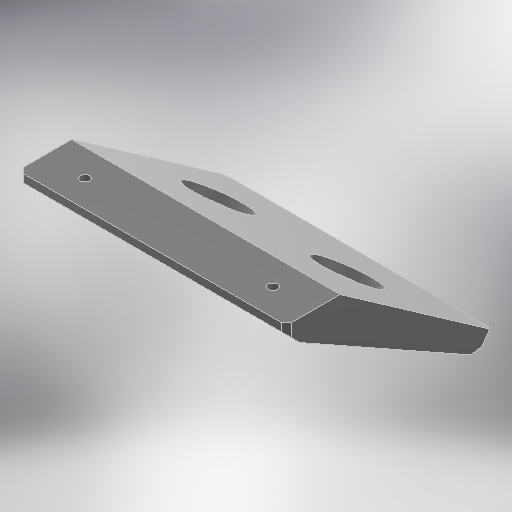
# Autodesk Inventor part: 3D_Estop-mount
Saved by Autodesk Inventor 2025.3 (Build 293356030, 356C)
## iProperties
Created: 2026-09-02
Part Number: 3D_Estop-mount
Material: 一般
Document SubType Name: Modeling
Designer: ibuki_ono
Density: 1 g/cm^3
Appearance: 滑らか - 黒
Author: ibuki_ono
## iProperties of the stored document 3D_Estop-mount_3D プリント.ipt
Created: 2026-09-04
Part Number: 3D_Estop-mount_3D プリント
Material: 一般
Document SubType Name: Modeling
Designer: ibuki_ono
Density: 1 g/cm^3
Appearance: 既定
Author: ibuki_ono
Autodesk Inventor part; units mm, degrees
ref_plane "YZ Plane" through (0, 0, 0) normal (1, 0, 0) x (0, 1, 0)
ref_plane "XZ Plane" through (0, 0, 0) normal (0, 1, 0) x (-1, 0, 0)
ref_plane "XY Plane" through (0, 0, 0) normal (0, 0, 1) x (1, 0, 0)
sketch "スケッチ1" plane through (0, 0, 0) normal (1, 0, 0) x (0, 1, 0)
  line L0 (0, 0) -> (-3, 0)
  line L1 (-3, 0) -> (-3, 20)
  line L2 (-3, 20) -> (0, 20)
  line L3 (0, 20) -> (0, 0)
  line L4 (0, 0) -> (-2.4575, 1.7207)
  line L5 (-2.4575, 1.7207) -> (-42.6078, -55.6199)
  line L6 (-42.6078, -55.6199) -> (-40.1504, -57.3406)
  line L7 (-40.1504, -57.3406) -> (0, 0)
  line L8 (0, 0) -> (3, 0) construction
  point P0 (-3, 0.9459)
  dimension "d0" = 3
  dimension "d1" = 20
  dimension "d2" = 3
  dimension "d3" = 145
  dimension "d4" = 70
  constraints: 18 end point, 4 parallel, 2 horizontal, 2 perpendicular, 1 equal length
  measures "d0" distance of L1.end L2.end
  measures "d1" distance of L0.end L1.end
  measures "d2" distance of L0.start L4.end
  measures "d3" angle of L8 L4
  measures "d4" distance of L5.end L4.end
extrude "押し出し1" add sketch "スケッチ1" along normal mid plane 100
sketch "スケッチ2" plane through (50, 0, 0) normal (1, 0, 0) x (0, 0, -1)
  line L0 (-20, -3) -> (-0.9459, -3) projected
  line L1 (-0.9459, -3) -> (55.6199, -42.6078) projected
  line L2 (-20, -3) -> (-15, -8)
  line L3 (-20, -3) -> (-12.9289, -3) construction
  line L4 (-15, -8) -> (48.6563, -43.8357)
  line L5 (48.6563, -43.8357) -> (55.6199, -42.6078)
  point P0 (0, 0)
  dimension "d7" = 45
  dimension "d8" = 45
  dimension "d9" = 5
  dimension "d10" = 5
  constraints: 8 end point, 1 equal length, 1 horizontal
  measures "d7" angle of L2 L3
  measures "d8" angle of L1 L5
  measures "d9" distance from line of L1 L4.end
  measures "d10" distance from line of L0 L2.end
extrude "押し出し2" add sketch "スケッチ2" against normal blind 5
chamfer "面取り1" distance 5 angle 45 2 edges at (45, -22.8039, -27.337) (45, -3, 10.4729)
mirror "ミラー1" about plane through (0, 0, 0) normal (1, 0, 0) of "押し出し2", "面取り1"
sketch "スケッチ3" plane through (-50, 0, 20) normal (0, 1, 0) x (1, 0, 0)
  line L0 (0, 0) -> (0, 20) projected
  line L1 (100, 20) -> (100, 0) projected
  line L2 (0, 10) -> (100, 10) construction
  line L3 (0, 20) -> (100, 20) construction
  point P0 (50, 20)
  point P1 (15, 10)
  point P2 (85, 10)
  point P3 (50, 20)
  point P4 (50, 20)
  dimension "d16" = 35
  dimension "d17" = 35
  constraints: 4 midpoint, 2 end point, 2 point on line
  measures "d16" horizontal distance of point (50, 20) point (15, 10)
  measures "d17" horizontal distance of point (85, 10) point (50, 20)
hole "穴1" at (-35, 0, 10) at (35, 0, 10) direction (0, -1, 0) diameter 3.5 end through all
sketch "スケッチ4" plane through (-50, 0, 0) normal (0, 0.8192, -0.5736) x (1, 0, 0)
  line L0 (100, 70) -> (100, 0) projected
  line L1 (0, 0) -> (0, 70) projected
  line L2 (100, 35) -> (0, 35) construction
  circle A0 centre (74, 35) radius 11
  circle A1 centre (26, 35) radius 11
  point P0 (50, 0)
  point P1 (50, 35)
  dimension "d25" = 22
  dimension "d26" = 22
  dimension "d27" = 24
  dimension "d28" = 24
  constraints: 3 midpoint, 2 centre point, 2 end point, 2 point on line
  measures "d25" diameter of A0
  measures "d26" diameter of A1
  measures "d27" distance of A0.centre point (50, 35)
  measures "d28" distance of point (50, 35) A1.centre
extrude "押し出し3" cut sketch "スケッチ4" against normal through all
chamfer "面取り2" distance 2 angle 45 4 edges at (50, -1.5, 20) (-50, -1.5, 20) (50, -41.3791, -56.4803) (-50, -41.3791, -56.4803)
equation "\"d2\" = d0"
equation "\"d10\" = d9"
equation "\"d17\" = d16"
equation "\"d28\" = d27"
